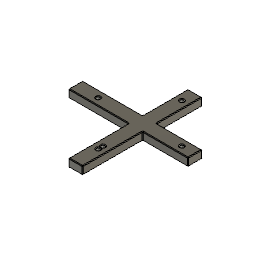
Bracket scale biaxial 4p0mm (Autodesk Fusion 360 design; units mm, degrees)
Autodesk Fusion 360 part; units mm, degrees
sketch "Sketch1" plane through (0, 0, 0) normal (0, 0, 1) x (1, 0, 0)
  line L0 (-50, 5.9) -> (50, 5.9)
  line L1 (50, 5.9) -> (50, -5.9)
  line L2 (50, -5.9) -> (-50, -5.9)
  line L3 (-50, -5.9) -> (-50, 5.9)
  circle A0 centre (39, 0) radius 1.6
  circle A1 centre (-27, 0) radius 1.6
  circle A2 centre (-31, 0) radius 1.6
  circle A3 centre (-35.6, 0) radius 1.6
  line L4 (0.2, 5.9) -> (12, 5.9)
  line L5 (12, 5.9) -> (12, -5.9)
  line L6 (12, -5.9) -> (0.2, -5.9)
  line L7 (0.2, -5.9) -> (0.2, 5.9)
  circle A4 centre (6.1, 0) radius 1.7
  line L8 (12, -56.1) -> (0.2, -56.1)
  line L9 (0.2, -56.1) -> (0.2, 43.9)
  line L10 (0.2, 43.9) -> (12, 43.9)
  line L11 (12, 43.9) -> (12, -56.1)
  circle A5 centre (6.1, -33.1) radius 1.6
  circle A6 centre (6.1, 32.9) radius 1.6
  circle A7 centre (6.1, -37.1) radius 1.6
  circle A8 centre (6.1, -41.7) radius 1.6
  dimension "d1" = 100
  dimension "d2" = 11.8
  dimension "d3" = 5.9
  dimension "d4" = 50
  dimension "d5" = 3.2
  dimension "d6" = 11
  dimension "d7" = 5.9
  dimension "d8" = 3.2
  dimension "d9" = 5.9
  dimension "d10" = 66
  dimension "d11" = 3.2
  dimension "d12" = 5.9
  dimension "d13" = 4
  dimension "d14" = 3.2
  dimension "d15" = 5.9
  dimension "d16" = 4.6
  dimension "d17" = 11.8
  dimension "d18" = 11.8
  dimension "d19" = 38
  dimension "d20" = 3.4
  dimension "d21" = 5.9
  dimension "d22" = 5.9
  dimension "d29" = 100
  dimension "d30" = 38
  dimension "d31" = 3.2
  dimension "d32" = 5.9
  dimension "d33" = 3.2
  dimension "d34" = 5.9
  dimension "d35" = 11
  dimension "d36" = 66
  dimension "d37" = 3.2
  dimension "d38" = 4
  dimension "d39" = 3.2
  dimension "d40" = 4.6
  dimension "d41" = 5.9
  dimension "d42" = 5.9
  dimension "d43" = 5.9
  constraint horizontal L0
  constraint vertical L1
  constraint horizontal L2
  constraint vertical L3
  constraint horizontal L4
  constraint vertical L5
  constraint horizontal L6
  constraint vertical L7
  constraint coincident L0 L4.start
  constraint horizontal L8
  constraint vertical L9
  constraint horizontal L10
  constraint vertical L11
  constraint coincident L5 L8.start
  measures "d1" distance of L0.start L0.end
  measures "d2" distance of L0.start L2.end
  measures "d3" distance of origin L0
  measures "d4" distance of origin L1
  measures "d5" diameter of A0
  measures "d6" distance of L1 A0.centre
  measures "d7" distance of L2 A0.centre
  measures "d8" diameter of A1
  measures "d9" distance of L0 A1.centre
  measures "d10" distance of A0.centre A1.centre
  measures "d11" diameter of A2
  measures "d12" distance of L0 A2.centre
  measures "d13" distance of A1.centre A2.centre
  measures "d14" diameter of A3
  measures "d15" distance of L0 A3.centre
  measures "d16" distance of A2.centre A3.centre
  measures "d17" distance of L4.start L4.end
  measures "d18" distance of L4.start L6.end
  measures "d19" distance of L1 L5
  measures "d20" diameter of A4
  measures "d21" distance of L0 A4.centre
  measures "d22" distance of L5 A4.centre
  measures "d29" distance of L8.start L10.end
  measures "d30" distance of L4 L10
  measures "d31" diameter of A5
  measures "d32" distance of L11 A5.centre
  measures "d33" diameter of A6
  measures "d34" distance of L11 A6.centre
  measures "d35" distance of L10 A6.centre
  measures "d36" distance of A5.centre A6.centre
  measures "d37" diameter of A7
  measures "d38" vertical distance of A5.centre A7.centre
  measures "d39" diameter of A8
  measures "d40" distance of A7.centre A8.centre
  measures "d41" distance of L11 A7.centre
  measures "d42" distance of L11 A8.centre
  measures "d43" distance of L9 A8.centre
extrude "Extrude1" add sketch "Sketch1" along normal blind 6.8 contours L0 L2 L3 L7 L9 | L0 L4 L9 L10 L11 | L0 L2 L4 L5 L6 L7 L9 L11 | L0 L1 L2 L5 L11 | L2 L6 L8 L9 L11 | A1 | A3 | A4 | A8
fillet "Fillet2" radius 0.5 19 faces at (0.2, -22.6333, 4.5333) (4.1333, 43.9, 2.2667) (-33.2667, -5.9, 4.5333) (8.0667, -56.1, 2.2667) (50, 1.9667, 2.2667) (0.2, 31.2333, 4.5333) (12, -39.3667, 4.5333) (-9.6667, 0, 6.8) (-29.408, -0.1593, 2.2667) (-16.5333, 5.9, 4.5333) (-50, -1.9667, 2.2667) (24.6667, -5.9, 4.5333) (40.592, -0.1593, 2.2667) (7.692, -33.2593, 2.2667) (7.698, 32.9798, 2.2667) (7.5052, -36.3348, 4.5333) (12, 18.5667, 4.5333) (37.3333, 5.9, 4.5333) (-9.6667, 0, 0)
